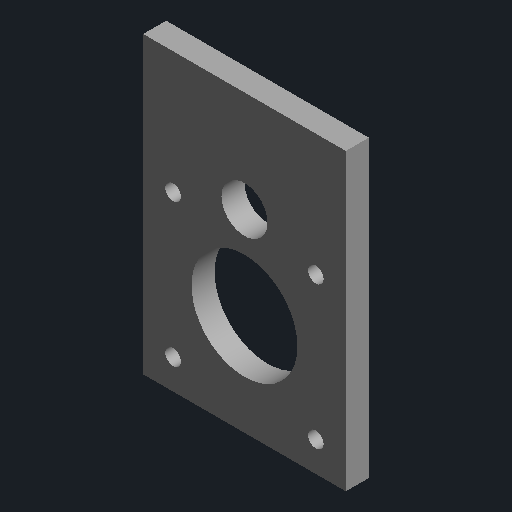
# Autodesk Inventor part: Soporte_Motor_NEMA17_2020
Saved by Autodesk Inventor 2027.2 (Build 312334000, 334)
## iProperties
Part Number: Soporte_Motor_NEMA17_2020
Material: Genérico
Document SubType Name: Modelado
Designer: Usuario
Appearance: Por defecto
Author: Usuario
Autodesk Inventor part; units mm, degrees
ref_plane "Plano YZ" through (0, 0, 0) normal (1, 0, 0) x (0, 1, 0)
ref_plane "Plano XZ" through (0, 0, 0) normal (0, 1, 0) x (-1, 0, 0)
ref_plane "Plano XY" through (0, 0, 0) normal (0, 0, 1) x (1, 0, 0)
sketch "Boceto1" plane through (0, 0, 0) normal (0, 0, 1) x (1, 0, 0)
  line L0 (-22, -22) -> (22, -22)
  line L1 (22, -22) -> (22, 42)
  line L2 (22, 42) -> (-22, 42)
  line L3 (-22, 42) -> (-22, -22)
  circle A0 centre (0, 0) radius 11.5
  circle A1 centre (-15.5, -15.5) radius 1.7
  circle A2 centre (15.5, -15.5) radius 1.7
  circle A3 centre (-15.5, 15.5) radius 1.7
  circle A4 centre (15.5, 15.5) radius 1.7
  circle A5 centre (0, 20) radius 5
  constraints: 8 end point, 6 centre point, 2 parallel, 1 horizontal, 1 perpendicular
extrude "Extrusión1" add sketch "Boceto1" along normal blind 5
